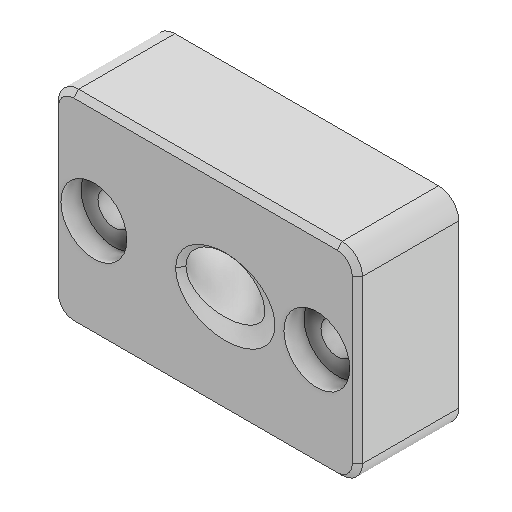
# Autodesk Inventor part: 3DP_PLA_Foldable_Leg_Brace_Mount_REVB
Saved by Autodesk Inventor 2027 (Build 310192060, 192F)
## iProperties
Created: 2026-02-22
Part Number: 3DP_PLA_Foldable_Leg_Brace_Mount_REVB
Material: Generic
Document SubType Name: Modeling
Designer: User
Density: 1 g/cm^3
Appearance: Default
Author: User
Autodesk Inventor part; units mm, degrees
ref_plane "YZ Plane" through (0, 0, 0) normal (1, 0, 0) x (0, 1, 0)
ref_plane "XZ Plane" through (0, 0, 0) normal (0, 1, 0) x (-1, 0, 0)
sketch "Sketch1" plane through (0, 0, 0) normal (0, 1, 0) x (-1, 0, 0)
  line L0 (30, 0) -> (0, 0)
  line L1 (0, 0) -> (0, -10)
  line L2 (0, -10) -> (30, -10)
  line L3 (30, -10) -> (30, 0)
  line L4 (7.7348, 0) -> (14.8059, -7.0711)
  line L5 (7.7348, 0) -> (17.7348, 0) construction
  dimension "d0" = 30
  dimension "d1" = 10
  dimension "d2" = 10
  dimension "d3" = 45
  constraints: 12 end point, 2 horizontal, 2 parallel, 1 coincident, 1 equal length, 1 perpendicular, 1 point on line
  measures "d0" distance of L2.end L1.end
  measures "d1" distance of L1.end L0.end
  measures "d2" distance of L4.start L4.end
  measures "d3" angle of L4 L5
extrude "Extrusion1" add sketch "Sketch1" along normal blind 20
ref_plane "Work Plane1" through (0, 0, 0) normal (0.7071, 0, 0.7071) x (0, 1, 0)
sketch "Sketch3" plane through (0, 0, 0) normal (0.7071, 0, 0.7071) x (0, 1, 0)
  circle A0 centre (10, 9.2132) radius 2.75
  line L0 (0, 21.2132) -> (0, 0) projected
  line L1 (0, 0) -> (20, 0) projected
  line L2 (20, 21.2132) -> (20, 0) projected
  line L3 (0, 21.2132) -> (20, 21.2132) projected
  dimension "d7" = 5.5
  dimension "d8" = 21.2132
  dimension "d9" = 12
  dimension "d10" = 10
  constraints: 1 centre point
  measures "d7" diameter of A0
  measures "d8" distance between parallel lines of L1 L3
  measures "d9" distance from line of L3 A0.centre
  measures "d10" distance from line of L0 A0.centre
extrude "Extrusion2" cut sketch "Sketch3" against normal blind 20 contours A0
fillet "Fillet1" radius 2 4 edges at (-30, 0, -5) (0, 0, -5) (0, 20, -5) (-30, 20, -5)
chamfer "Chamfer1" distance 1 angle 45 1 edges at (-13.0294, 7.25, 0)
sketch "Sketch4" plane through (-28, 0, 0) normal (0, 0, 1) x (1, 0, 0)
  arc A0 (0, 20) -> (-2, 18) centre (0, 18) ccw projected
  line L0 (-2, 2) -> (-2, 18) projected
  arc A1 (-2, 2) -> (0, 0) centre (0, 2) ccw projected
  line L1 (0, 0) -> (26, 0) projected
  arc A2 (26, 0) -> (28, 2) centre (26, 2) ccw projected
  line L2 (28, 2) -> (28, 18) projected
  arc A3 (28, 18) -> (26, 20) centre (26, 18) ccw projected
  line L3 (0, 20) -> (26, 20) projected
  point P0 (28, 0)
  point P1 (10.0815, 10)
  point P2 (2, 10)
  point P3 (24, 10)
  dimension "d17" = 10
  dimension "d18" = 10
  dimension "d19" = 20
  dimension "d20" = 4
  dimension "d21" = 4
  constraints: 1 other
  measures "d17" distance from line of L1 point (2, 10)
  measures "d18" distance from line of point (24, 10) L1
  measures "d19" distance between parallel lines of L1 L3
  measures "d20" distance from line of L0 point (2, 10)
  measures "d21" distance from line of L2 point (24, 10)
hole "Hole1" at (-26, 10, 0) at (-4, 10, 0) direction (0, 0, -1) diameter 3.2 end through all
hole "Hole2" at (-26, 10, 0) at (-4, 10, 0) direction (0, 0, -1) diameter 6.5 depth 2
chamfer "Chamfer2" distance 0.5 angle 45 8 edges at (-15, 0, 0) (-0.5858, 0.5858, 0) (0, 10, 0) (-0.5858, 19.4142, 0) (-15, 20, 0) (-29.4142, 19.4142, 0) (-30, 10, 0) (-29.4142, 0.5858, 0)
equation "\"d17\" = 0.5 * d19"
equation "\"d18\" = d17"
body "Solid1"
